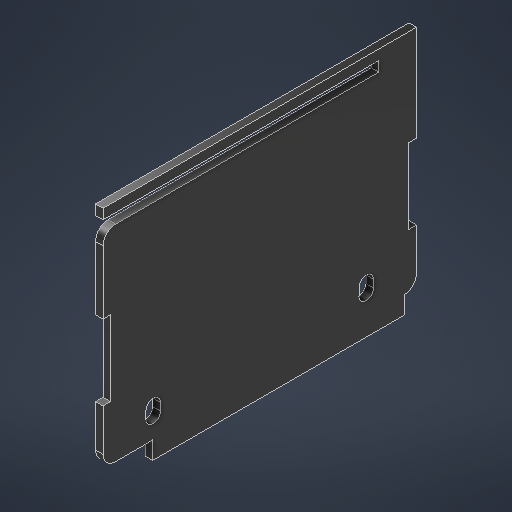
# Autodesk Inventor part: PowerBoxWidthFace
Saved by Autodesk Inventor 2027.1 (Build 311270010, 270A)
## iProperties
Created: 2026-10-13
Part Number: PowerBoxWidthFace
Material: MDF Medium Density Fiberboard
Document SubType Name: Modeling
Designer: SDS Scholar
Density: 0.8 g/cm^3
Appearance: Glossy - Black
Mass: 26.6923 g
Surface Area: 236.296 cm^2
Volume: 33.3654 cm^3
Author: SDS Scholar
Autodesk Inventor part; units mm, degrees
ref_plane "YZ Plane" through (0, 0, 0) normal (1, 0, 0) x (0, 1, 0)
ref_plane "XZ Plane" through (0, 0, 0) normal (0, 1, 0) x (-1, 0, 0)
ref_plane "XY Plane" through (0, 0, 0) normal (0, 0, 1) x (1, 0, 0)
sketch "Sketch1" plane through (0, 0, 0) normal (1, 0, 0) x (0, 1, 0)
  line L0 (44.5, 62.5) -> (-44.5, 62.5)
  line L1 (-44.5, 62.5) -> (-44.5, -62.5)
  line L2 (-44.5, -62.5) -> (44.5, -62.5)
  line L3 (44.5, -62.5) -> (44.5, 62.5)
  point P0 (0, 0)
  point P1 (44.5, 0)
  point P2 (0, -62.5)
  dimension "d0" = 125
  dimension "d1" = 89
  constraints: 8 end point, 2 midpoint, 2 parallel, 1 horizontal, 1 horizontal alignment, 1 perpendicular, 1 vertical alignment
  measures "d0" distance of L2.end L0.start
  measures "d1" distance of L1.end L2.end
extrude "Extrusion1" add sketch "Sketch1" along normal blind 3
sketch "Sketch2" plane through (3, 0, 0) normal (1, 0, 0) x (0, 0, -1)
  line L0 (-34.4771, 115.478) -> (-174.4771, 115.478)
  line L1 (-37.4771, 112.478) -> (-171.4771, 112.478)
  line L2 (-174.4771, 115.478) -> (-171.4771, 115.478)
  line L3 (-34.4771, 115.478) -> (-37.4771, 115.478)
  line L4 (-34.4771, 115.478) -> (-174.4771, 115.478)
  line L5 (-174.4771, 115.478) -> (-34.4771, 115.478)
  line L6 (-171.4771, 112.478) -> (-37.4771, 112.478)
  line L7 (-174.4771, 115.478) -> (-171.4771, 115.478)
  line L8 (-34.4771, 115.478) -> (-37.4771, 115.478)
  line L9 (-37.4771, 115.478) -> (-37.4771, 112.478)
  line L10 (-77.7771, 112.478) -> (-77.7771, 115.478)
  line L11 (-77.7771, 115.478) -> (-37.4771, 115.478)
  line L12 (-77.7771, 115.478) -> (-77.7771, 112.478)
  line L13 (-77.7771, 112.478) -> (-131.1771, 112.478)
  line L14 (-131.1771, 115.478) -> (-131.1771, 112.478)
  line L15 (-131.1771, 112.478) -> (-131.1771, 115.478)
  line L16 (-131.1771, 115.478) -> (-77.7771, 115.478)
  line L17 (-131.1771, 112.478) -> (-171.4771, 112.478)
  line L18 (-171.4771, 115.478) -> (-131.1771, 115.478)
  line L19 (-171.4771, 112.478) -> (-171.4771, 115.478)
  line L20 (-37.4771, 112.478) -> (-77.7771, 112.478)
  line L21 (62.5, 44.5) -> (-62.5, 44.5) projected
  line L22 (-62.5, 44.5) -> (-19.2, 44.5)
  line L23 (-19.2, 44.5) -> (-19.2, 47.5)
  line L24 (-19.2, 47.5) -> (-62.5, 47.5)
  line L25 (-62.5, 47.5) -> (-62.5, 44.5)
  line L26 (62.5, 44.5) -> (19.2, 44.5)
  line L27 (19.2, 44.5) -> (19.2, 47.5)
  line L28 (19.2, 47.5) -> (62.5, 47.5)
  line L29 (62.5, 47.5) -> (62.5, 44.5)
  line L30 (-19.2, 44.5) -> (19.2, 44.5)
  line L31 (19.2, 44.5) -> (19.2, 47.5)
  line L32 (19.2, 47.5) -> (-19.2, 47.5)
  line L33 (-19.2, 47.5) -> (-19.2, 44.5)
  line L34 (-62.5, 44.5) -> (-62.5, -44.5) projected
  line L35 (-62.5, -44.5) -> (62.5, -44.5) projected
  line L36 (-62.5, 44.5) -> (62.5, 44.5)
  line L37 (62.5, 44.5) -> (62.5, -44.5)
  line L38 (62.5, -44.5) -> (-62.5, -44.5)
  line L39 (-62.5, -44.5) -> (-62.5, 44.5)
  line L40 (59.5, 44.5) -> (59.5, -31.5)
  line L41 (59.5, -31.5) -> (-59.5, -31.5)
  line L42 (-59.5, -31.5) -> (-59.5, 44.5)
  line L43 (-62.5, 44.5) -> (-59.5, 44.5)
  line L44 (-59.5, 44.5) -> (-59.5, 14.2)
  line L45 (-59.5, 14.2) -> (-62.5, 14.2)
  line L46 (-62.5, 14.2) -> (-62.5, 44.5)
  line L47 (-59.5, 14.2) -> (-62.5, 14.2)
  line L48 (-62.5, 14.2) -> (-62.5, -15.8)
  line L49 (-62.5, -15.8) -> (-59.5, -15.8)
  line L50 (-59.5, -15.8) -> (-59.5, 14.2)
  line L51 (-59.5, -15.8) -> (-62.5, -15.8)
  line L52 (-62.5, -15.8) -> (-62.5, -44.5)
  line L53 (-62.5, -44.5) -> (-59.5, -44.5)
  line L54 (-59.5, -44.5) -> (-59.5, -15.8)
  line L55 (59.5, 44.5) -> (62.5, 44.5)
  line L56 (62.5, 44.5) -> (62.5, 14.2)
  line L57 (62.5, 14.2) -> (59.5, 14.2)
  line L58 (59.5, 14.2) -> (59.5, 44.5)
  line L59 (59.5, 14.2) -> (62.5, 14.2)
  line L60 (62.5, 14.2) -> (62.5, -15.8)
  line L61 (62.5, -15.8) -> (59.5, -15.8)
  line L62 (59.5, -15.8) -> (59.5, 14.2)
  line L63 (59.5, -15.8) -> (62.5, -15.8)
  line L64 (62.5, -15.8) -> (62.5, -44.5)
  line L65 (62.5, -44.5) -> (59.5, -44.5)
  line L66 (59.5, -44.5) -> (59.5, -15.8)
  line L67 (-62.5, 47.5) -> (-59.5, 47.5)
  line L68 (-59.5, 47.5) -> (-59.5, 44.5)
  line L69 (-59.5, 44.5) -> (-62.5, 44.5)
  line L70 (-62.5, 44.5) -> (-62.5, 47.5)
  line L71 (59.5, 47.5) -> (62.5, 47.5)
  line L72 (62.5, 47.5) -> (62.5, 44.5)
  line L73 (62.5, 44.5) -> (59.5, 44.5)
  line L74 (59.5, 44.5) -> (59.5, 47.5)
  point P0 (0, 0)
  point P1 (-104.4771, 145.0926)
  point P2 (-35.9771, 115.478)
  point P3 (-59.5, -44.5)
  point P4 (59.5, -31.5)
  point P5 (59.5, -15.8)
  point P6 (59.5, 14.2)
  point P7 (59.5, 44.5)
  point P8 (59.5, 44.5)
  point P9 (19.2, 44.5)
  point P10 (-59.5, 44.5)
  point P11 (-59.5, 44.5)
  point P12 (-19.2, 44.5)
  dimension "d4" = 43.3
  dimension "d5" = 43.3
  dimension "d6" = 3
  dimension "d7" = 3
  dimension "d8" = 30.3
  dimension "d9" = 30
  dimension "d10" = 30.3
  constraints: 144 end point, 25 parallel, 12 horizontal, 12 perpendicular, 11 point on line
  measures "d4" distance of L24.end L23.end
  measures "d5" distance of L27.end L28.end
  measures "d6" distance between parallel lines of L32 L30
  measures "d7" distance between parallel lines of L39 L42
  measures "d8" distance of L43.end L44.end
  measures "d9" distance of L48.end L47.end
  measures "d10" distance of L55.end L56.end
extrude "Extrusion3" cut sketch "Sketch2" against normal through all contours L37 L61 L40 L57 | L42 L49 L34 L45
sketch "Sketch3" plane through (3, 0, 0) normal (1, 0, 0) x (0, 0, -1)
  line L0 (59.5, 14.2) -> (62.5, 14.2) projected
  line L1 (62.5, 14.2) -> (62.5, 44.5) projected
  line L2 (62.5, 44.5) -> (-62.5, 44.5) projected
  line L3 (-62.5, 44.5) -> (-62.5, 14.2) projected
  line L4 (-62.5, 14.2) -> (-59.5, 14.2) projected
  line L5 (-59.5, 14.2) -> (-59.5, -15.8) projected
  line L6 (-59.5, -15.8) -> (-62.5, -15.8) projected
  line L7 (-62.5, -15.8) -> (-62.5, -44.5) projected
  line L8 (-62.5, -44.5) -> (62.5, -44.5) projected
  line L9 (62.5, -44.5) -> (62.5, -15.8) projected
  line L10 (62.5, -15.8) -> (59.5, -15.8) projected
  line L11 (59.5, -15.8) -> (59.5, 14.2) projected
  line L12 (-62.5, -37.5) -> (62.5, -37.5)
  line L13 (-62.5, -37.5) -> (-42.65, -37.5)
  line L14 (-42.65, -37.5) -> (-42.65, -44.5)
  line L15 (-42.65, -44.5) -> (-62.5, -44.5)
  line L16 (-62.5, -44.5) -> (-62.5, -37.5)
  line L17 (-42.65, -37.5) -> (-22.35, -37.5)
  line L18 (-22.35, -37.5) -> (-22.35, -44.5)
  line L19 (-22.35, -44.5) -> (-42.65, -44.5)
  line L20 (-42.65, -44.5) -> (-42.65, -37.5)
  line L21 (17.65, -37.5) -> (17.65, -44.5)
  line L22 (-2.65, -37.5) -> (-2.65, -44.5)
  line L23 (57.65, -37.5) -> (57.65, -44.5)
  line L24 (37.35, -37.5) -> (37.35, -44.5)
  point P0 (0, 0)
  point P1 (57.65, -37.5)
  point P2 (37.35, -44.5)
  point P3 (37.35, -37.5)
  point P4 (17.65, -37.5)
  point P5 (-2.65, -37.5)
  point P6 (-22.35, -37.5)
  point P7 (-42.65, -37.5)
  dimension "d15" = 7
  dimension "d16" = 19.85
  dimension "d17" = 20.3
  dimension "d20" = 40
  constraints: 26 end point, 4 parallel, 4 point on line, 3 horizontal, 3 perpendicular, 12 other
  measures "d15" distance between parallel lines of L8 L12
  measures "d16" distance between parallel lines of L7 L14
  measures "d17" distance between parallel lines of L14 L18
  measures "d20" distance of L17.end L21.start
extrude "Extrusion4" cut sketch "Sketch3" against normal through all contours L9 L8 L23 L12 | L12 L14 L8 L7
sketch "Sketch4" plane through (3, 0, 0) normal (1, 0, 0) x (0, 0, -1)
  line L0 (-42.5, -29) -> (-42.5, -26) construction
  line L1 (-39.6, -29) -> (-39.6, -26)
  line L2 (-45.4, -26) -> (-45.4, -29)
  arc A0 (-45.4, -29) -> (-39.6, -29) centre (-42.5, -29) ccw
  arc A1 (-39.6, -26) -> (-45.4, -26) centre (-42.5, -26) ccw
  line L3 (-62.5, -15.8) -> (-62.5, -37.5) projected
  line L4 (-62.5, -37.5) -> (-42.65, -37.5) projected
  line L5 (62.5, 44.5) -> (-62.5, 44.5) projected
  line L6 (0, 44.5) -> (0, -45.3782) construction
  line L7 (42.5, -29) -> (42.5, -26) construction
  line L8 (39.6, -29) -> (39.6, -26)
  line L9 (45.4, -26) -> (45.4, -29)
  arc A2 (39.6, -29) -> (45.4, -29) centre (42.5, -29) ccw
  arc A3 (45.4, -26) -> (39.6, -26) centre (42.5, -26) ccw
  point P0 (0, 0)
  point P1 (-42.5, -27.5)
  point P2 (26.7, 44.5)
  point P3 (-26.7, 44.5)
  point P4 (42.5, -27.5)
  dimension "d27" = 3
  dimension "d28" = 5.8
  dimension "d29" = 20
  dimension "d30" = 8.5
  constraints: 18 end point, 8 point on circle, 7 symmetric about line, 4 centre point, 4 tangent, 2 midpoint, 2 vertical, 1 parallel, 2 other
  measures "d27" distance of L0.start L0.end
  measures "d28" diameter of A1
  measures "d29" distance between parallel lines of L3 L0
  measures "d30" distance from line of L4 L0.start
extrude "Extrusion5" cut sketch "Sketch4" against normal through all
fillet "Fillet1" radius 5 4 edges at (1.5, 44.5, 62.5) (1.5, 44.5, -62.5) (1.5, -37.5, 62.5) (1.5, -37.5, -62.5)
sketch "Sketch5" plane through (3, 0, 0) normal (1, 0, 0) x (0, 0, -1)
  arc A0 (39.6, -29) -> (45.4, -29) centre (42.5, -29) ccw projected
  line L0 (39.6, -29) -> (39.6, -26) projected
  arc A1 (45.4, -26) -> (39.6, -26) centre (42.5, -26) ccw projected
  line L1 (45.4, -26) -> (45.4, -29) projected
  line L2 (-45.4, -29) -> (-45.4, -26) projected
  arc A2 (-39.6, -26) -> (-45.4, -26) centre (-42.5, -26) ccw projected
  line L3 (-39.6, -26) -> (-39.6, -29) projected
  arc A3 (-45.4, -29) -> (-39.6, -29) centre (-42.5, -29) ccw projected
  arc A4 (57.65, -37.5) -> (62.5, -32.5023) centre (57.5, -32.5023) ccw projected
  line L4 (62.5, -32.5023) -> (62.5, -15.8) projected
  line L5 (62.5, -15.8) -> (59.5, -15.8) projected
  line L6 (59.5, -15.8) -> (59.5, 14.2) projected
  line L7 (59.5, 14.2) -> (62.5, 14.2) projected
  line L8 (62.5, 14.2) -> (62.5, 39.5) projected
  arc A5 (62.5, 39.5) -> (57.5, 44.5) centre (57.5, 39.5) ccw projected
  line L9 (57.5, 44.5) -> (-57.5, 44.5) projected
  arc A6 (-57.5, 44.5) -> (-62.5, 39.5) centre (-57.5, 39.5) ccw projected
  line L10 (-62.5, 39.5) -> (-62.5, 14.2) projected
  line L11 (-62.5, 14.2) -> (-59.5, 14.2) projected
  line L12 (-59.5, 14.2) -> (-59.5, -15.8) projected
  line L13 (-59.5, -15.8) -> (-62.5, -15.8) projected
  line L14 (-62.5, -15.8) -> (-62.5, -32.5) projected
  arc A7 (-62.5, -32.5) -> (-57.5, -37.5) centre (-57.5, -32.5) ccw projected
  line L15 (-57.5, -37.5) -> (-42.65, -37.5) projected
  line L16 (-42.65, -37.5) -> (-42.65, -44.5) projected
  line L17 (-42.65, -44.5) -> (57.65, -44.5) projected
  line L18 (57.65, -44.5) -> (57.65, -37.5) projected
  line L19 (62.5, 39.5) -> (62.5, 52.5)
  line L20 (62.5, 52.5) -> (-62.5, 52.5)
  line L21 (-62.5, 52.5) -> (-62.5, 48.5)
  line L22 (-62.5, 48.5) -> (47.5, 48.5)
  line L23 (47.5, 48.5) -> (47.5, 44.5)
  point P0 (0, 0)
  point P1 (-62.5, 50.5)
  dimension "d36" = 4
  dimension "d37" = 4
  dimension "d38" = 15
  constraints: 10 end point, 2 perpendicular, 1 horizontal, 1 horizontal alignment, 1 midpoint, 1 point on line, 1 vertical, 1 vertical alignment
  measures "d36" distance of L22.end L23.end
  measures "d37" distance of L20.end L21.end
  measures "d38" distance between parallel lines of L19 L23
extrude "Extrusion6" add sketch "Sketch5" against normal blind 3 contours A5 L9 L23 L22 L21 L20 L19
equation "\"d0\" = BoxesWidth"
equation "\"d15\" = BaseWoodThickness"
equation "\"GridProcutClearance\" = 5"
equation "\"GridBorderThickness\" = 5"
equation "\"GridBorderFillets\" = 7"
equation "\"GridTotalSize\" = 65"
equation "\"GridRobotClearance\" = 65"
equation "\"AluminiumExtrusionClearance\" = 35"
equation "\"BaseTotalLength\" = 885"
equation "\"WorkspaceLength\" = 515"
equation "\"WorkspaceHeight\" = 183"
equation "\"AxesBaseFillet\" = 15"
equation "\"Zaxis\" = 197"
equation "\"ProductTotalHeight\" = 45"
equation "\"VerticalStroke\" = 105"
equation "\"BackArea\" = 165"
equation "\"CylinderStroke\" = 75"
equation "\"BoxesWidth\" = 125"
equation "\"BaseWoodThickness\" = 7"
equation "\"kerf\" = 1.5"
equation "\"Kerf\" = 0.3"
equation "\"RxThickness\" = 1.8"
equation "\"support_2\" = 265"
body "Solid1"
